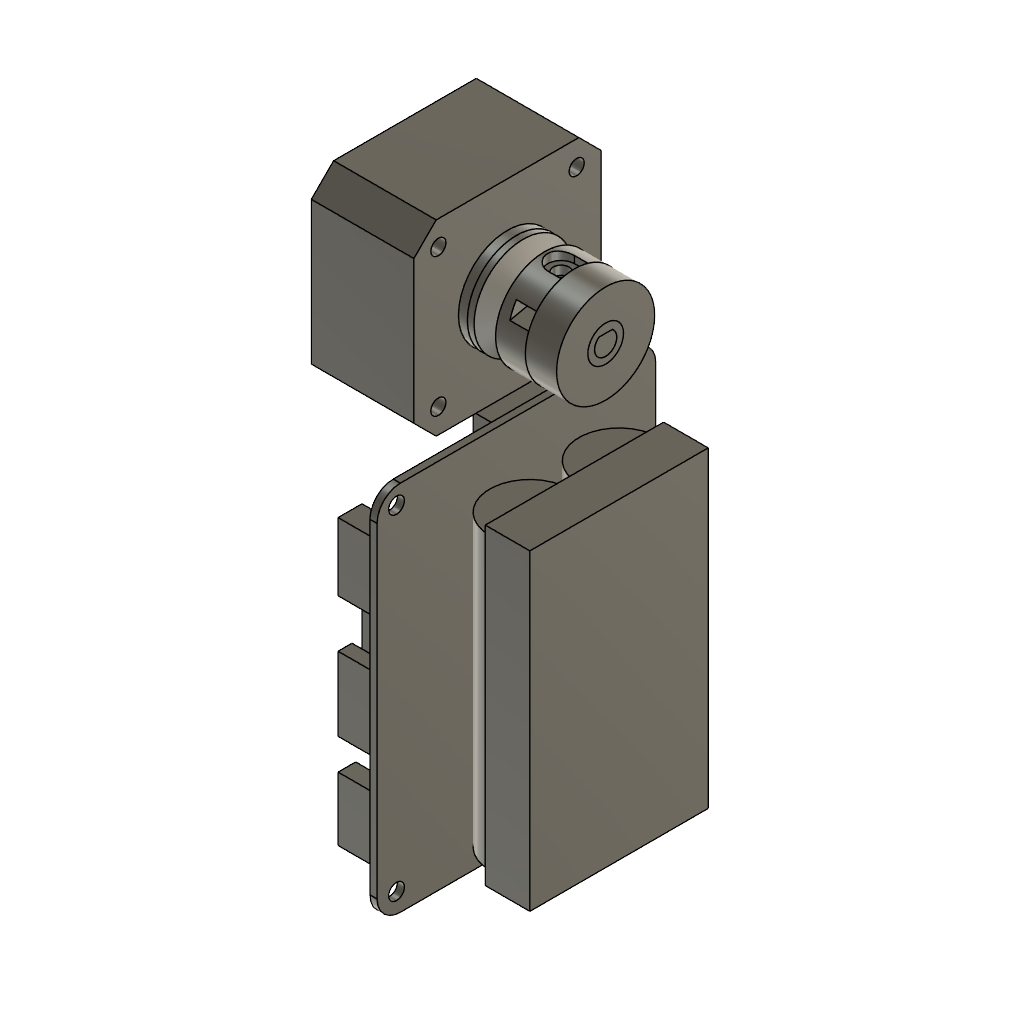
CurtainOpenerCase v1 (Autodesk Fusion 360 design; units mm, degrees)
part number: 2026-10-11-20-30-46-222
part number: 2026-10-11-20-39-21-226
part number: 2026-10-11-20-45-21-115
part number: 2026-10-12-17-45-10-322
part number: 2026-10-12-17-47-16-941
part number: 2026-10-14-17-03-01-915
part number: 2026-10-14-17-41-07-719
part number: 2026-10-14-20-53-17-655
part number: 2026-10-14-20-53-21-428
part number: 2026-10-14-20-53-23-899
Autodesk Fusion 360 part; units mm, degrees
sketch "Sketch2" plane through (0, 0, 0) normal (0, 0, 1) x (1, 0, 0) in component "PCB"
  circle A0 centre (92.7915, 74.8863) radius 1.7708
  circle A1 centre (92.7915, 20.7198) radius 1.7708
  circle A2 centre (17.7917, 74.8863) radius 1.7708
  circle A3 centre (97.2333, 36.1323) radius 6.25
  line L0 (97.2727, 74.0508) -> (97.2727, 21.9677)
  line L1 (13.9396, 21.9677) -> (13.9396, 74.0508)
  line L2 (92.0644, 16.7593) -> (19.1479, 16.7593)
  line L3 (19.1479, 79.2592) -> (92.0644, 79.2592)
  arc A4 (92.0644, 79.2592) -> (97.2727, 74.0508) centre (92.0644, 74.0509) cw
  arc A5 (97.2727, 21.9677) -> (92.0644, 16.7593) centre (92.0644, 21.9676) cw
  arc A6 (19.1479, 16.7593) -> (13.9396, 21.9677) centre (19.1479, 21.9676) cw
  arc A7 (13.9396, 74.0508) -> (19.1479, 79.2592) centre (19.1479, 74.0509) cw
  line L4 (75.939, 26.332) -> (95, 26.332)
  line L5 (95, 26.332) -> (95, 45)
  line L6 (95, 45) -> (75.939, 45)
  line L7 (75.939, 45) -> (75.939, 26.332)
  line L8 (40.6884, 58.7915) -> (60.5363, 58.7915)
  line L9 (60.5363, 58.7915) -> (60.5363, 72.6437)
  line L10 (60.5363, 72.6437) -> (40.6884, 72.6437)
  line L11 (40.6884, 72.6437) -> (40.6884, 58.7915)
  line L12 (18.2562, 27.0556) -> (42.8593, 27.0556)
  line L13 (42.8593, 27.0556) -> (42.8593, 47.7305)
  line L14 (42.8593, 47.7305) -> (18.2562, 47.7305)
  line L15 (18.2562, 47.7305) -> (18.2562, 27.0556)
  line L16 (23.6316, 72.6437) -> (38.8277, 72.6437)
  line L17 (38.8277, 72.6437) -> (38.8277, 78.0191)
  line L18 (38.8277, 78.0191) -> (23.6316, 78.0191)
  line L19 (23.6316, 78.0191) -> (23.6316, 72.6437)
  line L20 (49.5786, 74.8863) -> (66.1185, 74.8863)
  line L21 (66.1185, 74.8863) -> (66.1185, 78.0191)
  line L22 (66.1185, 78.0191) -> (49.5786, 78.0191)
  line L23 (49.5786, 78.0191) -> (49.5786, 74.8863)
  line L24 (73.0446, 74.0509) -> (87.3102, 74.0509)
  line L25 (87.3102, 74.0509) -> (87.3102, 78.0191)
  line L26 (87.3102, 78.0191) -> (73.0446, 78.0191)
  line L27 (73.0446, 78.0191) -> (73.0446, 74.0509)
  point P0 (94.5623, 74.8863)
  point P1 (94.5623, 20.7198)
  point P2 (19.5625, 74.8863)
  point P3 (103.4833, 36.1323)
  constraint horizontal L4
  constraint vertical L5
  constraint horizontal L6
  constraint vertical L7
  constraint horizontal L8
  constraint vertical L9
  constraint horizontal L10
  constraint vertical L11
  constraint horizontal L12
  constraint vertical L13
  constraint horizontal L14
  constraint vertical L15
  constraint horizontal L16
  constraint vertical L17
  constraint horizontal L18
  constraint vertical L19
  constraint horizontal L20
  constraint vertical L21
  constraint horizontal L22
  constraint vertical L23
  constraint horizontal L24
  constraint vertical L25
  constraint horizontal L26
  constraint vertical L27
extrude "Extrude1" add sketch "Sketch2" along normal blind 1.6 contours A3 L0 L1 L2 L3 A4 A5 A6 A7 L4 L5 L6 L7 | A3 L4 L5 L6 L7 | L8 L9 L10 L11 | L12 L13 L14 L15 | L16 L17 L18 L19 | L20 L21 L22 L23 | L24 L25 L26 L27 makes body 1 in component "PCB"
extrude "Extrude2" add sketch "Sketch2" along normal blind 10 contours A3 L4 L5 L6 L7 | L8 L9 L10 L11 | L12 L13 L14 L15 | L16 L17 L18 L19 | L20 L21 L22 L23 | L24 L25 L26 L27 bodies 1 in component "PCB"
sketch "Base" plane through (0, 0, 0) normal (0, 0, 1) x (1, 0, 0) in component "Nema17_Pancake"
  line L0 (0, 0) -> (42, 0)
  line L1 (42, 0) -> (42, 42)
  line L2 (42, 42) -> (0, 42)
  line L3 (0, 42) -> (0, 0)
  line L4 (12.9, 0) -> (29.1, 0)
  line L5 (29.1, 0) -> (29.1, -5.5)
  line L6 (29.1, -5.5) -> (12.9, -5.5)
  line L7 (12.9, -5.5) -> (12.9, 0)
  line L8 (42, 21) -> (21, 21) construction
  line L9 (21, 21) -> (0, 21) construction
  line L10 (21, 21) -> (21, 0) construction
  line L11 (21, -5.5) -> (21, 0) construction
  line L12 (21, 21) -> (21, 42) construction
  point P0 (21, 21)
  dimension "d14" = 42
  dimension "d15" = 42
  dimension "d28" = 16.2
  dimension "d32" = 5.5
  constraint horizontal L0
  constraint vertical L1
  constraint horizontal L2
  constraint vertical L3
  constraint coincident L0.start L3.end
  constraint horizontal L4
  constraint vertical L5
  constraint horizontal L6
  constraint vertical L7
  constraint coincident L0 L4.start
  constraint coincident L1 L8.start
  constraint perpendicular L1 L8
  constraint coincident L3 L9.end
  constraint perpendicular L3 L9
  constraint equal L8 L9
  constraint midpoint L0 L10.end
  constraint midpoint L6 L11.start
  constraint perpendicular L0 L11
  constraint midpoint L2 L12.end
  constraint equal L10 L12
  constraint coincident P0 L8.end
  measures "d14" distance of L0.start L0.end
  measures "d15" distance of L0.start L2.end
  measures "d28" distance of L4.start L4.end
  measures "d32" distance of L4.end L5.end
extrude "Extrude1'" add sketch "Base" along normal blind 23 separate body contours L0 L1 L2 L3 L4 makes body 2 in component "Nema17_Pancake"
extrude "Extrude3" add sketch "Base" along normal blind 5 contours L0 L4 L5 L6 L7 bodies 2 in component "Nema17_Pancake"
sketch "Top" plane through (0, 0, 23) normal (0, 0, 1) x (-1, 0, 0) in component "Nema17_Pancake"
  line L0 (0, -42) -> (0, 0)
  line L1 (0, 0) -> (-42, 0)
  line L2 (-42, 0) -> (-42, -42)
  line L3 (-42, -42) -> (0, -42)
  line L4 (-21, 0) -> (-21, -42) construction
  line L5 (0, -21) -> (-42, -21) construction
  circle A0 centre (-21, -21) radius 11
  circle A1 centre (-21, -21) radius 2.5
  line L6 (-19.5, -23) -> (-22.5, -23)
  line L7 (-18.5, -18.5) -> (-23.4104, -18.5) construction
  circle A2 centre (-5.5, -5.5) radius 1.7
  circle A3 centre (-36.5, -5.5) radius 1.7
  circle A4 centre (-5.5, -36.5) radius 1.7
  circle A5 centre (-36.5, -36.5) radius 1.7
  dimension "d33" = 22
  dimension "d34" = 5
  dimension "d35" = 4.5
  dimension "d43" = 3.4
  dimension "d44" = 15.5
  dimension "d45" = 15.5
  dimension "d48" = -31
  dimension "d49" = -31
  constraint midpoint L1 L4.start
  constraint midpoint L3 L4.end
  constraint midpoint L0 L5.start
  constraint midpoint L2 L5.end
  constraint midpoint L5 A0.centre
  constraint concentric A0 A1
  constraint coincident A1 L6.start
  constraint coincident A1 L6.end
  constraint horizontal L6
  constraint horizontal L7
  constraint tangent A1 L7
  measures "d33" diameter of A0
  measures "d34" diameter of A1
  measures "d35" distance of L6 L7
  measures "d43" diameter of A2
  measures "d44" distance of L5 A2.centre
  measures "d45" distance of L4 A2.centre
extrude "Extrude4" add sketch "Top" along normal blind 2 contours A0 bodies 2 in component "Nema17_Pancake"
extrude "Extrude5" add sketch "Top" along normal blind 22 contours A1 L6 picked at (-21.6191, -21.8516) bodies 2 in component "Nema17_Pancake"
extrude "Extrude6" add sketch "Top" along normal blind 5 contours A1 L6 picked at (-21.3999, -23.0645) bodies 2 in component "Nema17_Pancake"
extrude "Extrude7" cut sketch "Top" against normal blind 4.5 contours A2 | A3 | A4 | A5 bodies 2 in component "Nema17_Pancake"
chamfer "Chamfer2" distance 5 angle 45 4 edges at (42, 42, 11.5) (0, 42, 11.5) (0, 0, 11.5) (42, 0, 11.5) tangent chain off on bodies 2 in component "Nema17_Pancake"
sketch "Sketch1" plane through (0, 0, 0) normal (1, 0, 0) x (0, 1, 0) in component "Batteries"
  line L0 (0, 0) -> (40, 0)
  line L1 (40, 0) -> (40, 10)
  line L2 (40, 10) -> (0, 10)
  line L3 (0, 10) -> (0, 0)
  circle A0 centre (10, 10) radius 9
  circle A1 centre (30, 10) radius 9
  dimension "d67" = 40
  dimension "d68" = 10
  dimension "d69" = 18
  dimension "d70" = 18
  dimension "d71" = 10
  dimension "d72" = 10
  constraint horizontal L0
  constraint vertical L1
  constraint horizontal L2
  constraint vertical L3
  constraint coincident L0.start L3.end
  constraint coincident L2 A1.centre
  constraint coincident L2 A0.centre
  measures "d67" distance of L0.start L0.end
  measures "d68" distance of L0.start L2.end
  measures "d69" diameter of A0
  measures "d70" diameter of A1
  measures "d71" distance of L1 A1.centre
  measures "d72" distance of L3 A0.centre
extrude "Extrude1''" add sketch "Sketch1" along normal blind 70 separate body contours L0 L1 L2 L3 A0 A1 | L2 A0 | L2 A1 picked at (10.6676, 7.0752) picked at (27.7011, 6.6281) makes body 3 in component "Batteries"
extrude "Extrude2'" add sketch "Sketch1" along normal blind 65 from surface at 2.5 contours L2 A0 | L2 A1 picked at (8.904, 12.7926) picked at (32.4962, 13.3422) bodies 3 in component "Batteries"
sketch "Sketch2 (2)" plane through (0, 0, 0) normal (1, 0, 0) x (0, 1, 0) in component "Case-OLD"
  line L0 (0, 0) -> (70, 0) construction
  line L1 (70, 0) -> (70, 135) construction
  line L2 (70, 135) -> (0, 135) construction
  line L3 (0, 135) -> (0, 0) construction
  point P0 (35, 108)
  point P1 (35, 45)
  dimension "d82" = 70
  dimension "d83" = 135
  dimension "d84" = 35
  dimension "d85" = 35
  dimension "d87" = 27
  dimension "d88" = 45
  constraint horizontal L0
  constraint vertical L1
  constraint horizontal L2
  constraint vertical L3
  constraint coincident L0.start L3.end
  measures "d82" distance of L0.start L0.end
  measures "d83" distance of L0.start L2.end
  measures "d84" distance of L3 P1
  measures "d85" distance of L3 P0
  measures "d87" distance of L2 P0
  measures "d88" distance of L0 P1
sketch "Sketch3" plane through (0, 0, 0) normal (1, 0, 0) x (0, 1, 0) in component "Case-OLD"
  line L0 (0, 0) -> (70, 0)
  line L1 (70, 0) -> (70, 90)
  line L2 (70, 90) -> (0, 90)
  line L3 (0, 90) -> (0, 0)
  line L4 (0, 90) -> (10, 135)
  line L5 (70, 90) -> (60, 135)
  line L6 (60, 135) -> (10, 135)
  dimension "d93" = 70
  dimension "d94" = 90
  constraint horizontal L0
  constraint vertical L1
  constraint horizontal L2
  constraint vertical L3
  constraint coincident L0.start L3.end
  constraint parallel L2 L6
  measures "d93" distance of L0.start L0.end
  measures "d94" distance of L0.start L2.end
sketch "Sketch1 (2)" plane through (0, 0, 0) normal (1, 0, 0) x (0, 1, 0) in component "Gear"
  circle A0 centre (0, 0) radius 2.5
  line L0 (-1.5, 2) -> (1.5, 2)
  line L1 (-3.932, -2.5) -> (4.4404, -2.5) construction
  circle A1 centre (0, 0) radius 20
  dimension "d95" = 5
  dimension "d96" = 4.5
  constraint coincident A0.centre A1.centre
  constraint coincident A0 L0.start
  constraint coincident A0 L0.end
  constraint horizontal L0
  constraint tangent A0 L1
  constraint horizontal L1
  constraint concentric A0 A1
  measures "d95" diameter of A0
  measures "d96" distance of L0 L1
sketch "Sketch2 (3)" plane through (0, 0, 0) normal (0, 0, 1) x (1, 0, 0) in component "Gear"
  line L0 (0, -11) -> (0, 11)
  line L1 (0, 0) -> (20, 0)
  line L2 (0, 2) -> (20, 2) construction
  line L3 (3.9115, 20.0673) -> (3.9115, 2) construction
  line L4 (3.9115, 2) -> (6.3231, 11)
  line L5 (3.9115, 2) -> (1.5, 11)
  line L6 (0, 11) -> (20, 11) construction
  line L7 (0, 11) -> (1.5, 11)
  line L8 (6.3231, 11) -> (7.8231, 11)
  line L9 (7.8231, 11) -> (7.8231, 4)
  line L10 (7.8231, 4) -> (20, 4)
  line L11 (20, 4) -> (20, 0)
  line L12 (13, 4) -> (13, 11)
  line L13 (7.8231, 11) -> (13, 11)
  dimension "d97" = 22
  dimension "d98" = 20
  dimension "d99" = 2
  dimension "d100" = 15
  dimension "d101" = 15
  dimension "d102" = 11
  dimension "d103" = 20
  dimension "d104" = 1.5
  dimension "d105" = 1.5
  dimension "d133" = 7
  dimension "d147" = 4
  constraint vertical L0
  constraint coincident L1.start origin
  constraint perpendicular L0 L1
  constraint coincident L0 L2.start
  constraint perpendicular L0 L2
  constraint coincident L2 L3.end
  constraint perpendicular L2 L3
  constraint coincident L1.start L0
  constraint perpendicular L0 L6
  constraint coincident L4.end L6
  constraint coincident L5.end L6
  constraint parallel L6 L8
  constraint perpendicular L6 L9
  constraint perpendicular L9 L10
  constraint coincident L10 L12.start
  constraint perpendicular L10 L12
  measures "d97" distance of L0.start L0.end
  measures "d98" distance of L1.start L1.end
  measures "d99" distance of L1 L2
  measures "d100" angle of L3 L4
  measures "d101" angle of L3 L5
  measures "d102" distance of L0.end L1
  measures "d103" distance of L0.end L6.end
  measures "d104" distance of L0.end L5.end
  measures "d105" distance of L4.end L8.end
  measures "d133" distance of L11 L12
  measures "d147" distance of L1 L10
sketch "Sketch1 (3)" plane through (0, 0, 0) normal (1, 0, 0) x (0, 1, 0) in component "608 Bearing"
  circle A0 centre (0, 0) radius 4
  circle A1 centre (0, 0) radius 11
  dimension "d106" = 8
  dimension "d107" = 22
  constraint coincident A0.centre A1.centre
  measures "d106" diameter of A0
  measures "d107" diameter of A1
extrude "Extrude1'''" add sketch "Sketch1 (3)" along normal blind 7 separate body makes body 4 in component "608 Bearing"
revolve "Revolve1" add sketch "Sketch2 (3)" angle 360 about axis through (0, 0, 0) along (1, 0, 0) separate body makes body 5 in component "Gear"
fillet "Fillet1" radius 0.5 1 edges at (3.9115, -0.7232, 1.8647) on bodies 5 in component "Gear"
extrude "Extrude1''''" cut sketch "Sketch1 (2)" along normal blind 25 contours A0 L0 picked at (-0.7283, 0.7637) bodies 5 in component "Gear"
sketch "Sketch3 (2)" plane through (0, 0, 0) normal (0, 0, 1) x (1, 0, 0) in component "Gear"
  line L0 (13, -4) -> (20, -4)
  line L1 (20, -4) -> (20, 4)
  line L2 (13, 4) -> (20, 4)
  line L3 (6.3231, 11) -> (13, 11)
  line L4 (4.3945, 3.8024) -> (6.3231, 11)
  arc A0 (3.4286, 3.8024) -> (4.3945, 3.8024) centre (3.9115, 3.9319) ccw
  line L5 (3.4286, 3.8024) -> (1.5, 11)
  line L6 (0, 11) -> (1.5, 11)
  line L7 (0, -11) -> (0, 11)
  line L8 (0, -11) -> (1.5, -11)
  line L9 (3.4286, -3.8024) -> (1.5, -11)
  arc A1 (4.3945, -3.8024) -> (3.4286, -3.8024) centre (3.9115, -3.9319) ccw
  line L10 (4.3945, -3.8024) -> (6.3231, -11)
  line L11 (6.3231, -11) -> (13, -11)
  line L12 (20, 4) -> (13, 4)
  circle A2 centre (10, 0) radius 3
  circle A3 centre (10, 0) radius 1.75
  line L13 (9.0226, -11.733) -> (6.5246, 2.4335)
  line L14 (6.5246, 2.4335) -> (12.4335, 3.4754)
  line L15 (12.4335, 3.4754) -> (14.9314, -10.6911)
  line L16 (9.0226, -11.733) -> (14.9314, -10.6911)
  line L17 (10, 0) -> (12.9544, 0.5209) construction
  line L18 (10, 0) -> (9.4791, 2.9544) construction
  line L19 (13.5, 7) -> (6.5, 7)
  line L20 (6.5, 7) -> (6.5, -7)
  line L21 (6.5, -7) -> (13.5, -7)
  line L22 (13.5, -7) -> (13.5, 7)
  line L23 (13.5, 7) -> (6.5, -7) construction
  line L24 (6.5, 7) -> (13.5, -7) construction
  line L25 (0, 0) -> (20, 0) construction
  line L26 (13, -11) -> (13, -4)
  line L27 (13, 4) -> (13, 11)
  point P0 (10, 0)
  dimension "d115" = 7
  dimension "d116" = 6
  dimension "d117" = 10
  dimension "d118" = 3.5
  dimension "d124" = 90
  dimension "d125" = 80
  dimension "d126" = 3
  dimension "d128" = 3
  dimension "d129" = 6
  dimension "d134" = 7
  dimension "d135" = 14
  constraint coincident L1.end L2.end
  constraint perpendicular L1 L12
  constraint concentric A2 A3
  constraint perpendicular L13 L14
  constraint perpendicular L14 L15
  constraint coincident P0 A2.centre
  constraint coincident L15 L17.end
  constraint perpendicular L15 L17
  constraint midpoint L14 L18.end
  constraint horizontal L19
  constraint perpendicular L19 L20
  constraint parallel L19 L21
  constraint parallel L20 L22
  constraint coincident L23 P0
  constraint coincident L24 P0
  constraint coincident L25.start origin
  constraint midpoint L1 L25.end
  constraint coincident P0 L25
  measures "d115" distance of L1.end L2.start
  measures "d116" diameter of A2
  measures "d117" distance of L1 P0
  measures "d118" diameter of A3
  measures "d124" angle of L13 L16
  measures "d125" angle of L0 L13
  measures "d126" distance of P0 L17.end
  measures "d128" distance of P0 L18.end
  measures "d129" distance of L13 L15
  measures "d134" distance of L20.end L21.end
  measures "d135" distance of L19.end L20.end
extrude "Extrude2''" cut sketch "Sketch3 (2)" along normal blind 12 contours A3 bodies 5 in component "Gear"
extrude "Extrude3'" cut sketch "Sketch3 (2)" along normal blind 6 from surface at 9 contours A2 bodies 5 in component "Gear"
extrude "Extrude4'" cut sketch "Sketch3 (2)" along normal blind 3 from surface at 4 contours L0 A2 L13 L15 L21 L22 L26 | L0 L21 L22 L26 | L0 L15 L22 | L0 L11 L13 L15 L16 L21 L22 L26 | L11 L13 L21 L26 | A2 | A2 L14 L15 | A2 L13 L14 bodies 5 in component "Gear"
sketch "Sketch5" plane through (0, 0, 9) normal (0, 0, 1) x (-1, 0, 0) in component "Gear"
  circle A0 centre (-10, 0) radius 1.75
  circle A1 centre (-10, 0) radius 3
  line L0 (-10, -3) -> (-13.5, -3)
  line L1 (-13.5, -3) -> (-13.5, 3)
  line L2 (-13.5, 3) -> (-10, 3)
  line L3 (-10, 3) -> (-10, -3)
  constraint horizontal L0
  constraint vertical L1
  constraint horizontal L2
  constraint vertical L3
  constraint coincident A1 L0.start
extrude "Extrude7'" cut sketch "Sketch5" along normal blind 6 contours A0 L3 | A0 A1 L3 | A1 L0 L1 L2 picked at (-10.9302, -0.2598) picked at (-10.6157, -2.5018) bodies 5 in component "Gear"
combine "Combine1" [suppressed] in component "Gear"
sketch "Sketch4" plane through (0, 0, 0) normal (1, 0, 0) x (0, 1, 0)
  line L0 (0, 0) -> (70, 0)
  line L1 (70, 0) -> (70, 135)
  line L2 (70, 135) -> (0, 135)
  line L3 (0, 135) -> (0, 0)
  line L4 (0, 88) -> (70, 88)
  line L5 (0, 88) -> (8, 135)
  line L6 (70, 88) -> (62, 135)
  circle A0 centre (35, 110.75) radius 11
  line L7 (51, 89.75) -> (56, 94.75)
  line L8 (56, 94.75) -> (56, 126.75)
  line L9 (56, 126.75) -> (51, 131.75)
  line L10 (51, 131.75) -> (19, 131.75)
  line L11 (19, 131.75) -> (14, 126.75)
  line L12 (14, 126.75) -> (14, 94.75)
  line L13 (14, 94.75) -> (19, 89.75)
  line L14 (19, 89.75) -> (51, 89.75)
  circle A1 centre (19.5, 126.25) radius 1.7
  circle A2 centre (50.5, 126.25) radius 1.7
  circle A3 centre (19.5, 95.25) radius 1.7
  circle A4 centre (50.5, 95.25) radius 1.7
  circle A5 centre (35, 110.75) radius 15
  arc A6 (53.1268, 3.3334) -> (40.6271, 3.3334) centre (46.877, 3.3728) ccw
  line L15 (53.1268, 3.3334) -> (61.0416, 3.3334)
  arc A7 (61.0416, 3.3334) -> (66.2499, 8.5417) centre (61.0416, 8.5417) ccw
  line L16 (66.2499, 8.5417) -> (66.2499, 81.4583)
  arc A8 (66.2499, 81.4583) -> (61.0416, 86.6666) centre (61.0416, 81.4583) ccw
  line L17 (61.0416, 86.6666) -> (8.9584, 86.6666)
  arc A9 (8.9584, 86.6666) -> (3.7501, 81.4583) centre (8.9584, 81.4583) ccw
  line L18 (3.7501, 81.4583) -> (3.7501, 8.5417)
  arc A10 (3.7501, 8.5417) -> (8.9584, 3.3334) centre (8.9584, 8.5417) ccw
  line L19 (8.9584, 3.3334) -> (40.6271, 3.3334)
  circle A11 centre (8.1229, 82.8145) radius 1.7708
  circle A12 centre (8.1229, 7.8146) radius 1.7708
  circle A13 centre (62.2895, 7.8146) radius 1.7708
  circle A14 centre (8.1229, 82.8145) radius 2
  circle A15 centre (62.2895, 7.8146) radius 2
  circle A16 centre (8.1229, 7.8146) radius 2
  circle A17 centre (8.1229, 82.8145) radius 5
  circle A18 centre (62.2895, 7.8146) radius 5
  circle A19 centre (8.1229, 7.8146) radius 5
  line L20 (4, 79.9858) -> (4, 10.6434)
  line L21 (11.3553, 4) -> (59.0571, 4)
  line L22 (66, 11.1661) -> (66, 84)
  line L23 (12.9803, 84) -> (66, 84)
  line L24 (55, -10) -> (15, -10)
  line L25 (15, -10) -> (0, 0)
  line L26 (55, -10) -> (70, 0)
  arc A20 (8.1229, 2.8146) -> (62.2895, 2.8146) centre (35.2062, 140) ccw
  line L27 (8.1229, 2.8146) -> (8.1229, 7.8146) construction
  line L28 (62.2895, 2.8146) -> (62.2895, 7.8146) construction
  line L29 (13.1229, 7.8146) -> (13.1229, 1.9216)
  line L30 (57.2895, 7.8146) -> (57.2895, 1.9216)
  line L31 (62.2895, 7.8146) -> (57.2895, 7.8146) construction
  line L32 (62, 135) -> (47, 142)
  line L33 (23, 142) -> (8, 135)
  line L34 (23, 142) -> (47, 142)
  dimension "d152" = 70
  dimension "d153" = 135
  dimension "d154" = 47
  dimension "d155" = 30
  dimension "d156" = 4
  dimension "d157" = 4
  dimension "d158" = 4
  dimension "d159" = 10
  dimension "d160" = 10
  dimension "d161" = 10
  dimension "d162" = 4
  dimension "d163" = 4
  dimension "d166" = 4
  dimension "d167" = 4
  dimension "d183" = 10
  dimension "d184" = 15
  dimension "d185" = 15
  dimension "d186" = 150
  dimension "d205" = 8
  dimension "d206" = 8
  dimension "d207" = 7
  dimension "d209" = 15
  dimension "d210" = 15
  constraint horizontal L0
  constraint vertical L1
  constraint horizontal L2
  constraint vertical L3
  constraint coincident L0.start L3.end
  constraint coincident L3 L4.start
  constraint coincident L1 L4.end
  constraint perpendicular L1 L4
  constraint coincident L2 L5.end
  constraint coincident L2 L6.end
  constraint concentric A0 A5
  constraint concentric A11 A14
  constraint concentric A13 A15
  constraint concentric A12 A16
  constraint concentric A11 A17
  constraint concentric A15 A18
  constraint concentric A12 A19
  constraint coincident A17 L20.start
  constraint coincident A19 L20.end
  constraint parallel L18 L20
  constraint coincident A19 L21.start
  constraint coincident A18 L21.end
  constraint perpendicular L20 L21
  constraint coincident A18 L22.start
  constraint parallel L16 L22
  constraint coincident A17 L23.start
  constraint horizontal L23
  constraint horizontal L24
  constraint coincident A19 A20.start
  constraint coincident A18 A20.end
  constraint coincident A12.centre A16.centre
  constraint vertical L27
  constraint coincident A13.centre A15.centre
  constraint vertical L28
  constraint coincident A19 L29.start
  constraint coincident A20 L29.end
  constraint tangent A19 L29
  constraint coincident A18 L30.start
  constraint coincident A20 L30.end
  constraint tangent A18 L30
  constraint horizontal L31
  constraint collinear A13.centre L29.start L30.start
  constraint coincident L5.end L33
  constraint horizontal L34
  measures "d152" distance of L0.start L0.end
  measures "d153" distance of L0.start L2.end
  measures "d154" distance of L2 L4
  measures "d155" diameter of A5
  measures "d156" diameter of A14
  measures "d157" diameter of A15
  measures "d158" diameter of A16
  measures "d159" diameter of A17
  measures "d160" diameter of A18
  measures "d161" diameter of A19
  measures "d162" distance of L0 L21
  measures "d163" distance of L3 L20
  measures "d166" distance of L1 L22
  measures "d167" distance of L4 L23
  measures "d183" distance of L0 L24
  measures "d184" horizontal distance of L0.start L24.end
  measures "d185" horizontal distance of L0.end L24.start
  measures "d186" distance of L24 A20.centre
  measures "d205" distance of L1.end L6.end
  measures "d206" distance of L2.end L5.end
  measures "d207" distance of L2 L34
  measures "d209" horizontal distance of L5.end L33.start
  measures "d210" horizontal distance of L6.end L32.end
extrude "Extrude1'''''" [suppressed]
extrude "Extrude2'''" [suppressed]
extrude "Extrude3''" [suppressed]
sketch "Sketch5 (2)" plane through (0, 0, 88) normal (0, 0, -1) x (1, 0, 0)
  line L0 (0, 0) -> (-25, 0)
  line L1 (-25, 0) -> (-25, -70)
  line L2 (-25, -70) -> (0, -70)
  line L3 (-25, -35) -> (-11, -35)
  line L4 (-11, -35) -> (-11, -21)
  line L5 (-11, -21) -> (-25, -21)
  line L6 (-25, -21) -> (-25, -35)
  line L7 (-25, -35) -> (-11, -35)
  line L8 (-11, -35) -> (-11, -49)
  line L9 (-11, -49) -> (-25, -49)
  line L10 (-25, -49) -> (-25, -35)
  line L11 (0, -70) -> (0, 0)
  dimension "d174" = 14
  dimension "d175" = 14
  dimension "d176" = 14
  dimension "d177" = 14
  constraint horizontal L3
  constraint vertical L4
  constraint horizontal L5
  constraint vertical L6
  constraint midpoint L1 L3.start
  constraint horizontal L7
  constraint vertical L8
  constraint horizontal L9
  constraint vertical L10
  measures "d174" distance of L3.start L5.end
  measures "d175" distance of L4.end L5.end
  measures "d176" distance of L3.start L3.end
  measures "d177" distance of L3.start L9.end
extrude "Extrude5'" [suppressed]
sketch "Sketch6" plane through (0, 0, 0) normal (-1, 0, 0) x (0, -1, 0)
  line L0 (-66, 84) -> (-12.9803, 84)
  arc A0 (-12.9803, 84) -> (-3.7501, 80.39) centre (-8.1229, 82.8145) ccw
  circle A1 centre (-8.1229, 82.8145) radius 2
  line L1 (-3, 85) -> (-3, 88)
  line L2 (-67, 85) -> (-67, 88)
  circle A2 centre (-52.5, -4.5) radius 5
  line L3 (-35, -10) -> (-35, 12.8656) construction
  line L4 (0, 88) -> (-70, 88)
  line L5 (-70, 88) -> (-70, 0)
  line L6 (-70, 0) -> (-55, -10)
  line L7 (-55, -10) -> (-15, -10)
  line L8 (-15, -10) -> (0, 0)
  line L9 (0, 0) -> (0, 88)
  circle A3 centre (-8.1229, 7.8146) radius 2
  circle A4 centre (-62.2895, 7.8146) radius 2
  line L10 (-66, 11.1661) -> (-66, 84)
  line L11 (-3.7501, 80.39) -> (-3.7501, 10.2391)
  arc A5 (-3.7501, 10.2391) -> (-13.1229, 7.8146) centre (-8.1229, 7.8146) ccw
  line L12 (-13.1229, 7.8146) -> (-13.1229, 1.9216)
  arc A6 (-57.2895, 1.9216) -> (-13.1229, 1.9216) centre (-35.2062, 140) ccw
  line L13 (-57.2895, 1.9216) -> (-57.2895, 7.8146)
  arc A7 (-57.2895, 7.8146) -> (-66, 11.1661) centre (-62.2895, 7.8146) ccw
  line L14 (-67, 85) -> (-67, 1.6056)
  line L15 (-67, 1.6056) -> (-54.0917, -7)
  line L16 (-54.0917, -7) -> (-15.9083, -7)
  line L17 (-15.9083, -7) -> (-3, 1.6056)
  line L18 (-3, 1.6056) -> (-3, 85)
  line L19 (-3, 85) -> (-67, 85)
  circle A8 centre (-17.5, -4.5) radius 5
  dimension "d187" = 10
  dimension "d189" = 17.5
  dimension "d194" = -3
  constraint collinear L2 L14
  constraint collinear L1 L18
  constraint symmetric A2 L3 A8
  measures "d187" diameter of A2
  measures "d189" distance of A2.centre L3
extrude "Extrude6'" [suppressed]
sketch "Sketch7" plane through (-25, 0, 0) normal (-1, 0, 0) x (0, -1, 0)
  line L0 (0, 88) -> (-8, 135)
  line L1 (-62, 135) -> (-70, 88)
  line L2 (-70, 88) -> (-70, 0)
  line L3 (-70, 0) -> (-55, -10)
  line L4 (-55, -10) -> (-15, -10)
  line L5 (-15, -10) -> (0, 0)
  line L6 (0, 0) -> (0, 88)
  line L7 (-3, 88) -> (-3, 1.6056)
  line L8 (-3, 1.6056) -> (-12.5054, -4.7314)
  arc A0 (-12.5054, -4.7314) -> (-21.8301, -7) centre (-17.5, -4.5) ccw
  line L9 (-21.8301, -7) -> (-48.1699, -7)
  arc A1 (-48.1699, -7) -> (-57.4946, -4.7314) centre (-52.5, -4.5) ccw
  line L10 (-57.4946, -4.7314) -> (-67, 1.6056)
  line L11 (-67, 1.6056) -> (-67, 88)
  line L12 (-67, 88) -> (-49, 88)
  line L13 (-49, 88) -> (-49, 89.75)
  line L14 (-49, 89.75) -> (-51, 89.75)
  line L15 (-51, 89.75) -> (-56, 94.75)
  line L16 (-56, 94.75) -> (-56, 126.75)
  line L17 (-56, 126.75) -> (-51, 131.75)
  line L18 (-51, 131.75) -> (-19, 131.75)
  line L19 (-19, 131.75) -> (-14, 126.75)
  line L20 (-14, 126.75) -> (-14, 94.75)
  line L21 (-14, 94.75) -> (-19, 89.75)
  line L22 (-19, 89.75) -> (-21, 89.75)
  line L23 (-21, 89.75) -> (-21, 88)
  line L24 (-21, 88) -> (-3, 88)
  circle A2 centre (-52.5, -4.5) radius 2
  circle A3 centre (-17.5, -4.5) radius 2
  circle A4 centre (-7.7, 94) radius 2
  circle A5 centre (-7.7, 94) radius 5
  line L25 (-35, 135) -> (-35, 92) construction
  circle A6 centre (-62.3, 94) radius 2
  line L26 (-8, 135) -> (-23, 142)
  line L27 (-23, 142) -> (-47, 142)
  line L28 (-47, 142) -> (-62, 135)
  circle A7 centre (-12.5, 131.5824) radius 5
  circle A8 centre (-12.5, 131.5824) radius 2
  circle A9 centre (-57.5, 131.5824) radius 2
  circle A10 centre (-57.5, 131.5824) radius 5
  circle A11 centre (-62.3, 94) radius 5
  dimension "d195" = 4
  dimension "d196" = 4
  dimension "d198" = 4
  dimension "d199" = 10
  dimension "d200" = 6
  dimension "d201" = 6.3
  dimension "d211" = 10
  dimension "d212" = 4
  dimension "d213" = 1.5
  constraint concentric A1 A2
  constraint concentric A0 A3
  constraint coincident A4.centre A5.centre
  constraint perpendicular L18 L25
  constraint symmetric A4 L25 A6
  constraint concentric A7 A8
  constraint symmetric L25 A8 A9
  constraint symmetric A5 L25 A11
  constraint symmetric L25 A7 A10
  constraint tangent L26 A7
  constraint tangent L28 A10
  measures "d195" diameter of A2
  measures "d196" diameter of A3
  measures "d198" diameter of A4
  measures "d199" diameter of A5
  measures "d200" distance of L24 A4.centre
  measures "d201" distance of L20 A4.centre
  measures "d211" diameter of A7
  measures "d212" diameter of A8
  measures "d213" distance of L20 A7.centre
extrude "Extrude7''" [suppressed]
sketch "Sketch10" plane through (3, 0, 0) normal (1, 0, 0) x (0, 1, 0)
  arc A0 (66, 11.1661) -> (57.2895, 7.8146) centre (62.2895, 7.8146) ccw
  line L0 (57.2895, 7.8146) -> (57.2895, 1.9216)
  arc A1 (13.1229, 1.9216) -> (57.2895, 1.9216) centre (35.2062, 140) ccw
  line L1 (13.1229, 1.9216) -> (13.1229, 7.8146)
  arc A2 (13.1229, 7.8146) -> (3.7501, 10.2391) centre (8.1229, 7.8146) ccw
  line L2 (3.7501, 10.2391) -> (3.7501, 80.39)
  arc A3 (3.7501, 80.39) -> (12.9803, 84) centre (8.1229, 82.8145) ccw
  line L3 (12.9803, 84) -> (66, 84)
  line L4 (66, 84) -> (66, 11.1661)
  circle A4 centre (8.1229, 7.8146) radius 2
  circle A5 centre (19.5, 95.25) radius 1.7
  circle A6 centre (50.5, 126.25) radius 1.7
  circle A7 centre (19.5, 126.25) radius 1.7
  circle A8 centre (50.5, 95.25) radius 1.7
  circle A9 centre (35, 110.75) radius 15
  circle A10 centre (8.1229, 82.8145) radius 2
  line L5 (70, 0) -> (70, 88)
  line L6 (70, 88) -> (62, 135)
  line L7 (62, 135) -> (47, 142)
  line L8 (47, 142) -> (23, 142)
  line L9 (23, 142) -> (8, 135)
  line L10 (8, 135) -> (0, 88)
  line L11 (0, 88) -> (0, 0)
  line L12 (0, 0) -> (15, -10)
  line L13 (15, -10) -> (55, -10)
  line L14 (55, -10) -> (70, 0)
  circle A11 centre (62.2895, 7.8146) radius 2
  circle A12 centre (12.5, 131.5824) radius 2
  circle A13 centre (7.7, 94) radius 2
  circle A14 centre (17.5, -4.5) radius 2
  circle A15 centre (57.5, 131.5824) radius 2
  circle A16 centre (62.3, 94) radius 2
  circle A17 centre (52.5, -4.5) radius 2
  line L15 (23.6655, 139) -> (10.6936, 132.9464)
  line L16 (10.6936, 132.9464) -> (3, 87.7465)
  line L17 (3, 87.7465) -> (3, 1.6056)
  line L18 (3, 1.6056) -> (15.9083, -7)
  line L19 (15.9083, -7) -> (54.0917, -7)
  line L20 (54.0917, -7) -> (67, 1.6056)
  line L21 (67, 1.6056) -> (67, 87.7465)
  line L22 (67, 87.7465) -> (59.3064, 132.9464)
  line L23 (59.3064, 132.9464) -> (46.3345, 139)
  line L24 (46.3345, 139) -> (23.6655, 139)
  dimension "d219" = -3
extrude "Extrude9" [suppressed]
sketch "Sketch14" plane through (3, 0, 0) normal (1, 0, 0) x (0, 1, 0)
  circle A0 centre (12.5, 131.5824) radius 2
  line L0 (11.6542, 133.3947) -> (10.6936, 132.9464)
  line L1 (10.6936, 132.9464) -> (3, 87.7465)
  line L2 (3, 87.7465) -> (3, 1.6056)
  line L3 (3, 1.6056) -> (15.9083, -7)
  line L4 (15.9083, -7) -> (54.0917, -7)
  line L5 (54.0917, -7) -> (67, 1.6056)
  line L6 (67, 1.6056) -> (67, 87.7465)
  line L7 (67, 87.7465) -> (59.3064, 132.9464)
  line L8 (59.3064, 132.9464) -> (58.3458, 133.3947)
  circle A1 centre (57.5, 131.5824) radius 2
  line L9 (58.3458, 133.3947) -> (46.3345, 139)
  line L10 (46.3345, 139) -> (23.6655, 139)
  line L11 (23.6655, 139) -> (11.6542, 133.3947)
  circle A2 centre (52.5, -4.5) radius 2
  circle A3 centre (62.3, 94) radius 2
  circle A4 centre (17.5, -4.5) radius 2
  circle A5 centre (7.7, 94) radius 2
  circle A6 centre (62.2895, 7.8146) radius 2
  circle A7 centre (8.1229, 82.8145) radius 2
  circle A8 centre (35, 110.75) radius 15
  circle A9 centre (50.5, 95.25) radius 1.7
  circle A10 centre (19.5, 126.25) radius 1.7
  circle A11 centre (50.5, 126.25) radius 1.7
  circle A12 centre (19.5, 95.25) radius 1.7
  circle A13 centre (8.1229, 7.8146) radius 2
  arc A14 (66, 11.1661) -> (57.2895, 7.8146) centre (62.2895, 7.8146) ccw
  line L12 (57.2895, 7.8146) -> (57.2895, 1.9216)
  arc A15 (13.1229, 1.9216) -> (57.2895, 1.9216) centre (35.2062, 140) ccw
  line L13 (13.1229, 1.9216) -> (13.1229, 7.8146)
  arc A16 (13.1229, 7.8146) -> (3.7501, 10.2391) centre (8.1229, 7.8146) ccw
  line L14 (3.7501, 10.2391) -> (3.7501, 80.39)
  arc A17 (3.7501, 80.39) -> (12.9803, 84) centre (8.1229, 82.8145) ccw
  line L15 (12.9803, 84) -> (66, 84)
  line L16 (66, 84) -> (66, 11.1661)
  circle A18 centre (8.1229, 82.8145) radius 5
  circle A19 centre (8.1229, 7.8146) radius 5
  circle A20 centre (62.2895, 7.8146) radius 5
  line L17 (57.2895, 7.8146) -> (57.2895, -4.8681)
  line L18 (13.1229, 7.8146) -> (13.1229, -5.1431)
  line L19 (3.7501, 10.2391) -> (3, 10.2391)
  line L20 (66, 11.1661) -> (67, 11.1661)
  line L21 (3.7501, 80.39) -> (3, 80.39)
  line L22 (8.0561, 87.814) -> (3, 87.7465)
  dimension "d249" = 10
  dimension "d250" = 10
  dimension "d251" = 10
  constraint concentric A7 A18
  constraint concentric A13 A19
  constraint concentric A6 A20
  constraint coincident A14.end L12.start
  constraint coincident L5 L17.end
  constraint tangent A20 L17
  constraint parallel L12 L17
  constraint coincident L13.end A16.start
  constraint coincident L3 L18.end
  constraint tangent A16 L18
  constraint coincident A16.end L14.start
  constraint coincident L2 L19.end
  constraint perpendicular L2 L19
  constraint coincident A14.start L16.end
  constraint coincident L6 L20.end
  constraint perpendicular L6 L20
  constraint coincident L14.end A17.start
  constraint coincident L2 L21.end
  constraint perpendicular L2 L21
  constraint coincident A18 L22.start
  constraint coincident L1.end L2.start
  constraint tangent A18 L22
  measures "d249" diameter of A18
  measures "d250" diameter of A19
  measures "d251" diameter of A20
extrude "Extrude17" [suppressed]
sketch "Sketch8" plane through (3, 0, 0) normal (1, 0, 0) x (0, 1, 0)
  arc A0 (12.9803, 84) -> (8.0561, 87.814) centre (8.1229, 82.8145) ccw
  line L0 (12.9803, 84) -> (66, 84)
  line L1 (66, 84) -> (66, 11.1661)
  circle A1 centre (19.5, 95.25) radius 1.7
  circle A2 centre (50.5, 126.25) radius 1.7
  circle A3 centre (19.5, 126.25) radius 1.7
  circle A4 centre (50.5, 95.25) radius 1.7
  circle A5 centre (35, 110.75) radius 15
  circle A6 centre (7.7, 94) radius 2
  circle A7 centre (62.3, 94) radius 2
  circle A8 centre (35, 110.75) radius 15
  line L2 (23, 119.75) -> (23, 144)
  line L3 (23, 144) -> (47, 144)
  line L4 (47, 144) -> (47, 119.75)
  line L5 (59.3064, 132.9464) -> (58.3458, 133.3947)
  line L6 (46.3345, 139) -> (23.6655, 139)
  line L7 (10.6936, 132.9464) -> (3, 87.7465)
  line L8 (67, 11.1661) -> (67, 87.7465)
  circle A9 centre (12.5, 131.5824) radius 2
  line L9 (11.6542, 133.3947) -> (10.6936, 132.9464)
  line L10 (67, 87.7465) -> (59.3064, 132.9464)
  circle A10 centre (57.5, 131.5824) radius 2
  line L11 (58.3458, 133.3947) -> (46.3345, 139)
  line L12 (23.6655, 139) -> (11.6542, 133.3947)
  line L13 (66, 11.1661) -> (67, 11.1661)
  line L14 (3, 87.7465) -> (8.0561, 87.814)
  dimension "d217" = 24
  dimension "d218" = 12
  constraint coincident A5 L2.start
  constraint vertical L2
  constraint perpendicular L2 L3
  constraint coincident A5 L4.end
  constraint vertical L4
  measures "d217" distance of L2 L4
  measures "d218" distance of A5.centre L4
extrude "Extrude8" [suppressed]
sketch "Sketch16" plane through (0, 67, 0) normal (0, -1, 0) x (1, 0, 0)
  line L0 (0, 1.6056) -> (0, 88)
  line L1 (0, 88) -> (-25, 88)
  line L2 (-25, 88) -> (-25, 1.6056)
  line L3 (-25, 1.6056) -> (0, 1.6056)
  line L4 (-1, 43.3334) -> (-9, 43.3334)
  line L5 (-9, 43.3334) -> (-9, 53.3334)
  line L6 (-9, 53.3334) -> (-1, 53.3334)
  line L7 (-1, 53.3334) -> (-1, 43.3334)
  line L8 (-1.6, 5.6062) -> (-10, 5.6062)
  line L9 (-10, 24.6671) -> (-10, 5.6062)
  line L10 (-10, 27.5616) -> (-10, 24.6671)
  line L11 (-1.6, 27.5616) -> (-10, 27.5616)
  line L12 (-1.6, 34.4877) -> (-1.6, 27.5616)
  line L13 (-1.6, 34.4877) -> (-10, 34.4877)
  line L14 (-10, 40.0699) -> (-10, 34.4877)
  line L15 (-10, 57.7469) -> (-10, 40.0699)
  line L16 (-10, 82.35) -> (-10, 57.7469)
  line L17 (-1.6, 82.35) -> (-10, 82.35)
  line L18 (-1.6, 86.6666) -> (-1.6, 82.35)
  line L19 (0, 86.6666) -> (-1.6, 86.6666)
  line L20 (0, 81.4583) -> (0, 86.6666)
  line L21 (0, 8.5417) -> (0, 81.4583)
  line L22 (0, 3.3334) -> (0, 8.5417)
  line L23 (-1.6, 3.3334) -> (0, 3.3334)
  line L24 (-1.6, 5.6062) -> (-1.6, 3.3334)
  dimension "d259" = 40
  dimension "d260" = 10
  dimension "d261" = 8
  dimension "d262" = 1
  constraint horizontal L4
  constraint vertical L5
  constraint horizontal L6
  constraint vertical L7
  measures "d259" distance of L4 L23
  measures "d260" distance of L4.end L5.end
  measures "d261" distance of L5 L7
  measures "d262" distance of L7 L21
extrude "Extrude18" [suppressed]
sketch "Sketch18" plane through (0, 0, -10) normal (0, 0, -1) x (1, 0, 0)
  line L0 (-25, -55) -> (23, -55)
  line L1 (23, -55) -> (23, -15)
  line L2 (23, -15) -> (-25, -15)
  line L3 (-25, -15) -> (-25, -55)
  circle A0 centre (-15, -35) radius 6.15
  dimension "d271" = 12.3
  dimension "d272" = 10
  dimension "d273" = 20
  measures "d271" diameter of A0
  measures "d272" distance of L3 A0.centre
  measures "d273" distance of L2 A0.centre
extrude "Extrude20" [suppressed]
extrude "Extrude3'''" [no effect] in component "PCB"
sketch "Sketch11" plane through (-25, 0, 0) normal (-1, 0, 0) x (0, -1, 0)
  line L0 (-3, 88) -> (-3, 1.6056)
  line L1 (-3, 1.6056) -> (-12.5054, -4.7314)
  arc A0 (-12.5054, -4.7314) -> (-21.8301, -7) centre (-17.5, -4.5) ccw
  line L2 (-21.8301, -7) -> (-48.1699, -7)
  arc A1 (-48.1699, -7) -> (-57.4946, -4.7314) centre (-52.5, -4.5) ccw
  line L3 (-57.4946, -4.7314) -> (-67, 1.6056)
  line L4 (-67, 1.6056) -> (-67, 88)
  line L5 (-67, 88) -> (-49, 88)
  line L6 (-49, 88) -> (-49, 89.75)
  line L7 (-49, 89.75) -> (-51, 89.75)
  line L8 (-51, 89.75) -> (-56, 94.75)
  line L9 (-56, 94.75) -> (-56, 126.75)
  line L10 (-56, 126.75) -> (-51, 131.75)
  line L11 (-51, 131.75) -> (-19, 131.75)
  line L12 (-19, 131.75) -> (-14, 126.75)
  line L13 (-14, 126.75) -> (-14, 94.75)
  line L14 (-14, 94.75) -> (-19, 89.75)
  line L15 (-19, 89.75) -> (-21, 89.75)
  line L16 (-21, 89.75) -> (-21, 88)
  line L17 (-21, 88) -> (-3, 88)
  line L18 (0, 88) -> (-8, 135)
  line L19 (-8, 135) -> (-23, 142)
  line L20 (-23, 142) -> (-47, 142)
  line L21 (-47, 142) -> (-62, 135)
  line L22 (-62, 135) -> (-70, 88)
  line L23 (-70, 88) -> (-70, 0)
  line L24 (-70, 0) -> (-55, -10)
  line L25 (-55, -10) -> (-15, -10)
  line L26 (-15, -10) -> (0, 0)
  line L27 (0, 0) -> (0, 88)
  circle A2 centre (-12.5, 131.5824) radius 2
  circle A3 centre (-7.7, 94) radius 2
  circle A4 centre (-17.5, -4.5) radius 2
  circle A5 centre (-57.5, 131.5824) radius 2
  circle A6 centre (-62.3, 94) radius 2
  circle A7 centre (-52.5, -4.5) radius 2
extrude "Extrude10" [suppressed]
extrude "Extrude11" [suppressed]
extrude "Extrude12" [suppressed]
extrude "Extrude13" [suppressed]
sketch "Sketch13" plane through (23, 0, 0) normal (1, 0, 0) x (0, 1, 0)
  circle A0 centre (12.5, 131.5824) radius 2
  circle A1 centre (7.7, 94) radius 2
  line L0 (62, 135) -> (47, 142)
  line L1 (47, 142) -> (23, 142)
  line L2 (23, 142) -> (8, 135)
  line L3 (8, 135) -> (0, 88)
  line L4 (0, 88) -> (0, 0)
  line L5 (0, 0) -> (15, -10)
  line L6 (15, -10) -> (55, -10)
  line L7 (55, -10) -> (70, 0)
  line L8 (70, 0) -> (70, 88)
  line L9 (70, 88) -> (62, 135)
  circle A2 centre (57.5, 131.5824) radius 2
  line L10 (66.4182, 91.1645) -> (67, 87.7465)
  line L11 (67, 87.7465) -> (67, 1.6056)
  line L12 (67, 1.6056) -> (57.4946, -4.7314)
  arc A3 (57.4946, -4.7314) -> (48.1699, -7) centre (52.5, -4.5) ccw
  line L13 (48.1699, -7) -> (21.8301, -7)
  arc A4 (21.8301, -7) -> (12.5054, -4.7314) centre (17.5, -4.5) ccw
  line L14 (12.5054, -4.7314) -> (3, 1.6056)
  line L15 (3, 1.6056) -> (3, 87.7465)
  line L16 (3, 87.7465) -> (3.5818, 91.1645)
  arc A5 (3.5818, 91.1645) -> (4.7518, 98.0383) centre (7.7, 94) ccw
  line L17 (4.7518, 98.0383) -> (9.7506, 127.4061)
  arc A6 (9.7506, 127.4061) -> (15.8069, 135.3326) centre (12.5, 131.5824) ccw
  line L18 (15.8069, 135.3326) -> (23.6655, 139)
  line L19 (23.6655, 139) -> (46.3345, 139)
  line L20 (46.3345, 139) -> (54.1931, 135.3326)
  arc A7 (54.1931, 135.3326) -> (60.2494, 127.4061) centre (57.5, 131.5824) ccw
  line L21 (60.2494, 127.4061) -> (65.2482, 98.0383)
  arc A8 (65.2482, 98.0383) -> (66.4182, 91.1645) centre (62.3, 94) ccw
  circle A9 centre (62.3, 94) radius 2
  circle A10 centre (17.5, -4.5) radius 2
  circle A11 centre (52.5, -4.5) radius 2
  circle A12 centre (35, 110.75) radius 11
  circle A13 centre (35, 110.75) radius 5
  circle A14 centre (35, 110.75) radius 17.5
  circle A15 centre (35, 74) radius 1.7
  circle A16 centre (35, 18) radius 1.7
  line L22 (35, -10) -> (35, 75.3507) construction
  dimension "d235" = 10
  dimension "d236" = 35
  dimension "d241" = 3.4
  dimension "d242" = 3.4
  dimension "d243" = 56
  dimension "d244" = 25
  constraint concentric A12 A13
  constraint concentric A13 A14
  constraint midpoint L6 L22.start
  constraint perpendicular L13 L22
  constraint coincident A15.centre L22
  constraint coincident A16.centre L22
  measures "d235" diameter of A13
  measures "d236" diameter of A14
  measures "d241" diameter of A15
  measures "d242" diameter of A16
  measures "d243" distance of A15.centre A16.centre
  measures "d244" distance of L13 A16.centre
extrude "Extrude14" [suppressed]
extrude "Extrude15" [suppressed]
extrude "Extrude16" [suppressed]
sketch "Sketch20" plane through (23, 0, 0) normal (-1, 0, 0) x (0, -1, 0)
  circle A0 centre (-7.7, 94) radius 2
  line L0 (-62, 135) -> (-70, 88)
  line L1 (-70, 88) -> (-70, 0)
  line L2 (-70, 0) -> (-55, -10)
  line L3 (-55, -10) -> (-15, -10)
  line L4 (-15, -10) -> (0, 0)
  line L5 (0, 0) -> (0, 88)
  line L6 (0, 88) -> (-8, 135)
  line L7 (-8, 135) -> (-23, 142)
  line L8 (-23, 142) -> (-47, 142)
  line L9 (-47, 142) -> (-62, 135)
  circle A1 centre (-35, 18) radius 1.7
  circle A2 centre (-12.5, 131.5824) radius 2
  circle A3 centre (-17.5, -4.5) radius 2
  circle A4 centre (-57.5, 131.5824) radius 2
  circle A5 centre (-62.3, 94) radius 2
  circle A6 centre (-52.5, -4.5) radius 2
  circle A7 centre (-35, 74) radius 1.7
  circle A8 centre (-35, 110.75) radius 17.5
  line L10 (-70, 88) -> (0, 88)
  constraint coincident L0.end L1.start
  constraint coincident L5.end L6.start
extrude "Extrude21" [suppressed]
combine "Combine1'" [suppressed]
sketch "Sketch21" plane through (18.5, 0, 0) normal (-1, 0, 0) x (0, -1, 0)
  line L0 (-66.4182, 91.1645) -> (-66.9569, 88)
  line L1 (-66.9569, 88) -> (-3.0431, 88)
  line L2 (-3.0431, 88) -> (-3.5818, 91.1645)
  arc A0 (-4.7518, 98.0383) -> (-3.5818, 91.1645) centre (-7.7, 94) ccw
  line L3 (-4.7518, 98.0383) -> (-9.7506, 127.4061)
  arc A1 (-15.8069, 135.3326) -> (-9.7506, 127.4061) centre (-12.5, 131.5824) ccw
  line L4 (-15.8069, 135.3326) -> (-23.6655, 139)
  line L5 (-23.6655, 139) -> (-46.3345, 139)
  line L6 (-46.3345, 139) -> (-54.1931, 135.3326)
  arc A2 (-60.2494, 127.4061) -> (-54.1931, 135.3326) centre (-57.5, 131.5824) ccw
  line L7 (-60.2494, 127.4061) -> (-65.2482, 98.0383)
  arc A3 (-66.4182, 91.1645) -> (-65.2482, 98.0383) centre (-62.3, 94) ccw
  circle A4 centre (-35, 110.75) radius 17.5
  line L8 (-58.7293, 90.5) -> (-11.2707, 90.5)
  dimension "d285" = 2.5
  constraint coincident A3 L8.start
  constraint coincident A0 L8.end
  constraint horizontal L8
  measures "d285" distance of L1 L8
extrude "Extrude22" [suppressed]
chamfer "Chamfer1" [suppressed]
chamfer "Chamfer2'" [suppressed]
chamfer "Chamfer3" [suppressed]
chamfer "Chamfer4" [suppressed]
chamfer "Chamfer5" [suppressed]
chamfer "Chamfer6" [suppressed]
fillet "Fillet1'" [suppressed]
chamfer "Chamfer7" [suppressed]
combine "Combine2" [suppressed]
chamfer "Chamfer8" [suppressed]
copy_body "Body->Comp1" [suppressed] in component "Main Case"
copy_body "Body->Comp2" [suppressed] in component "Front Plate"
copy_body "Body->Comp3" [suppressed] in component "Back Plate"
component "PCB" placed x (0, 0, -1) y (0, -1, 0) z (-1, 0, 0) at (0, 83.0093, 100.6062)
component "Nema17_Pancake" placed x (0, 1, 0) y (0, 0, 1) z (1, 0, 0) at (-25, 14, 89.75)
component "Batteries" placed x (0, 0, 1) y (0, 1, 0) z (-1, 0, 0) at (23, 15, 12)
component "Case-OLD" placed x (1, 0, 0) y (0, 1, 0) z (0, 0, 1) at (0, 0, 0)
component "Gear" placed x (1, 0, 0) y (0, 1, 0) z (0, 0, 1) at (0, 35, 110.75)
component "608 Bearing" placed x (1, 0, 0) y (0, 1, 0) z (0, 0, 1) at (13, 35, 110.75)
equation "width = 70 mm"
equation "height = 135 mm"
equation "d82 = width"
equation "d83 = height"
equation "d84 = width / 2"
equation "d85 = width / 2"
equation "moff = 27 mm" comment "motor offset from edge"
equation "d87 = moff"
equation "d88 = pcboff"
equation "pcboff = 45 mm" comment "pcb offset from edge"
equation "pcbh = 90 mm" comment "pcb height"
equation "d93 = width"
equation "d94 = pcbh"
equation "d152 = width"
equation "d153 = height"
equation "d224 = panelthickness"
equation "d233 = panelthickness"
equation "panelthickness = 3.5 mm" comment "Side panel thickness"
named bodies: "Main Case", "Front Plate", "Back Plate"
